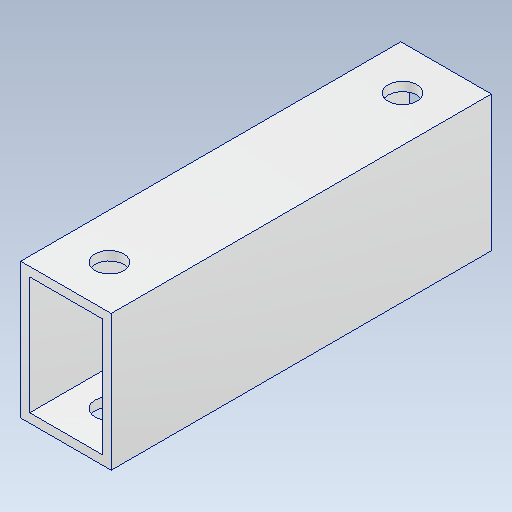
# Autodesk Inventor part: alsp_10_15_42_1
Saved by Autodesk Inventor 2027.1 (Build 311270010, 270A)
## iProperties
Created: 2026-10-29
Part Number: alsp_10_15_42_1
Material: アルミニウム 6061
Document SubType Name: Modeling
Designer: ug_nd
Density: 2.7 g/cm^3
Appearance: アルミニウム - フラット
Author: ug_nd
Autodesk Inventor part; units mm, degrees
ref_plane "YZ Plane" through (0, 0, 0) normal (1, 0, 0) x (0, 1, 0)
ref_plane "XZ Plane" through (0, 0, 0) normal (0, 1, 0) x (-1, 0, 0)
ref_plane "XY Plane" through (0, 0, 0) normal (0, 0, 1) x (1, 0, 0)
sketch "スケッチ1" plane through (0, 0, 0) normal (0, 0, 1) x (1, 0, 0)
  line L0 (-5, -7.5) -> (5, -7.5)
  line L1 (5, -7.5) -> (5, 7.5)
  line L2 (5, 7.5) -> (-5, 7.5)
  line L3 (-5, 7.5) -> (-5, -7.5)
  line L4 (-5, -7.5) -> (5, 7.5) construction
  line L5 (5, -7.5) -> (-5, 7.5) construction
  line L6 (-4, -6.5) -> (4, -6.5)
  line L7 (4, -6.5) -> (4, 6.5)
  line L8 (4, 6.5) -> (-4, 6.5)
  line L9 (-4, 6.5) -> (-4, -6.5)
  line L10 (-4, -6.5) -> (4, 6.5) construction
  line L11 (4, -6.5) -> (-4, 6.5) construction
  point P0 (0, 0)
  dimension "d0" = 10
  dimension "d1" = 15
  dimension "d2" = 1
  dimension "d3" = 1
  constraints: 24 end point, 4 midpoint, 4 parallel, 2 horizontal, 2 perpendicular
  measures "d0" distance of L1.end L2.end
  measures "d1" distance of L2.end L0.start
  measures "d2" distance between parallel lines of L8 L2
  measures "d3" distance between parallel lines of L3 L9
extrude "押し出し1" add sketch "スケッチ1" along normal mid plane 42
sketch "スケッチ2" plane through (-5, 7.5, 21) normal (0, 1, 0) x (1, 0, 0)
  line L0 (-99.3079, 21) -> (460.6921, 21) construction
  line L1 (5, 321) -> (5, -239) construction
  circle A0 centre (108.2477, 21) radius 200 construction
  line L2 (108.2477, 21) -> (8.2477, 194.2051) construction
  line L3 (108.2477, 21) -> (8.2477, -152.2051) construction
  line L4 (8.2477, 194.2051) -> (-38.1625, 21) construction
  line L5 (8.2477, -152.2051) -> (-38.1625, 21) construction
  line L6 (-27.9745, 203.9108) -> (-68.7385, 51.7775)
  line L7 (44.4699, 184.4994) -> (3.7059, 32.366)
  line L8 (-27.9745, 203.9108) -> (44.4699, 184.4994)
  circle A1 centre (5, 37.1957) radius 1.6
  circle A2 centre (5, 4.8043) radius 1.6
  point P0 (5, 21)
  dimension "d6" = 400
  dimension "d7" = 120
  dimension "d9" = 150
  dimension "d10" = 75
  dimension "d11" = 157.5
  dimension "d16" = 3.2
  dimension "d17" = 5
  constraints: 14 end point, 4 point on line, 4 symmetric about line, 2 centre point, 1 midpoint, 1 parallel, 4 other
  measures "d7" angle of L3 L2
  measures "d9" angle of L5 L4
  measures "d10" distance between parallel lines of L7 L6
  measures "d11" distance of L6.start L6.end
  measures "d16" diameter of A1
  measures "d17" distance of L7.end A1.centre
extrude "押し出し2" cut sketch "スケッチ2" against normal through all
